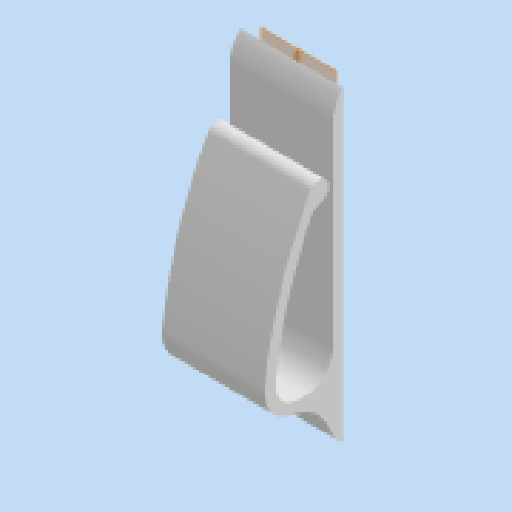
# Autodesk Inventor part: Pieza1
Saved by Autodesk Inventor 2026.3 (Build 303398000, 398)
## iProperties
Created: 2026-11-11
Part Number: Pieza1
Material: Genérico
Document SubType Name: Modeling
Designer: Hp
Density: 1 g/cm^3
Appearance: Valor por defecto
Author: Hp
Autodesk Inventor part; units mm, degrees
ref_plane "YZ Plane" through (0, 0, 0) normal (1, 0, 0) x (0, 1, 0)
ref_plane "XZ Plane" through (0, 0, 0) normal (0, 1, 0) x (-1, 0, 0)
ref_plane "Plano de trabajo1" through (0, 0, 0) normal (0, 0, 1) x (1, 0, 0)
sketch "Boceto1" plane through (0, 0, 0) normal (0, 0, 1) x (1, 0, 0)
  arc A0 (-5, -16) -> (5, -16) centre (0, -16) ccw projected
  line L0 (5, 16) -> (5, -16) projected
  arc A1 (5, 16) -> (-5, 16) centre (0, 16) ccw projected
  line L1 (-5, -16) -> (-5, 16) projected
  circle A2 centre (0, -16) radius 2.5 projected
  circle A3 centre (0, 16) radius 2.5 projected
  arc A4 (4.78, 16) -> (-4.78, 16) centre (0, 16) ccw
  line L2 (4.78, 16) -> (4.78, -16)
  arc A5 (-4.78, -16) -> (4.78, -16) centre (0, -16) ccw
  line L3 (-4.78, -16) -> (-4.78, 16)
  circle A6 centre (0, 16) radius 2.72
  circle A7 centre (0, -16) radius 2.72
  point P0 (0, 0)
  dimension "d0" = 0.22
  dimension "d1" = 0.22
  constraints: 4 centre point, 4 end point, 4 point on circle, 1 coincident, 1 equal radius, 3 other
  measures "d0" radial gap between concentric circles of A1 A4
  measures "d1" radial gap between concentric circles of A3 A6
ref_plane "Plano de trabajo2" through (-26.5719, -30.2815, 0.6) normal (0, 0, 1) x (1, 0, 0)
extrude "Extrusión1" add sketch "Boceto1" along normal blind 1 contours L2 A5 L3 A4
ref_plane "Plano de trabajo4" through (0, -16, 0) normal (-1, 0, 0) x (0, 0, 1)
sketch "Boceto4" plane through (0, 0, 1) normal (0, 0, 1) x (1, 0, 0)
  line L0 (7.5, 22.5) -> (-7.5, 22.5)
  line L1 (-7.5, 22.5) -> (-7.5, -22.5)
  line L2 (-7.5, -22.5) -> (7.5, -22.5)
  line L3 (7.5, -22.5) -> (7.5, 22.5)
  line L4 (0, -31.5) -> (0, 31.5) projected
  point P0 (0, 0)
  dimension "d22" = 45
  dimension "d23" = 15
  dimension "d24" = 7.5
  dimension "d25" = 22.5
  constraints: 8 end point, 2 parallel, 1 horizontal, 1 perpendicular
  measures "d22" distance of L2.end L0.start
  measures "d23" distance of L1.end L2.end
  measures "d24" distance between parallel lines of L3 L4
  measures "d25" distance from line of point (0, 0) L0
extrude "Extrusión4" add sketch "Boceto4" along normal blind 1.5
sketch "Boceto2" plane through (0, -16, 0) normal (-1, 0, 0) x (0, 0, 1)
  line L0 (2.5, 0.5467) -> (14.8168, 0.5467) construction
  line L1 (14.8168, 0.5467) -> (0.6, 37) construction
  arc A0 (7.5, 0.5467) -> (12.4705, 6.0892) centre (7.5, 5.5467) ccw
  arc A1 (12.4705, 6.0892) -> (5.825, 27.7031) centre (-47.1753, -0.4211) ccw
  arc A2 (12.1583, 7.3634) -> (3.8339, 2.1467) centre (7.5, 5.5467) ccw construction
  arc A3 (12.4705, 6.0892) -> (12.1583, 7.3634) centre (7.5, 5.5467) ccw
  arc A4 (10.8799, 5.9156) -> (4.4117, 26.9531) centre (-47.1753, -0.4211) ccw
  arc A5 (7.656, 2.1503) -> (7.6549, 2.1502) centre (7.5, 5.5467) ccw construction
  arc A6 (7.6549, 2.1502) -> (7.5, 2.1467) centre (7.5, 5.5467) ccw
  arc A7 (7.5, 2.1467) -> (7.656, 2.1503) centre (7.5, 5.5467) ccw
  line L2 (0.6, 37) -> (0, 37)
  arc A8 (5.825, 27.7031) -> (4.4117, 26.9531) centre (5.1183, 27.3281) ccw
  circle A9 centre (4.5, 27) radius 1.5
  arc A10 (5.6844, 24.4067) -> (4.2318, 25.5242) centre (3.8741, 23.5564) ccw
  line L3 (7.5, 0.5467) -> (2.5, 0.5467)
  line L4 (2.5, 2.1467) -> (7.5, 2.1467)
  line L5 (2.5, 0.5467) -> (2.5, 2.1467)
  line L6 (2.5, -6.5) -> (2.5, 38.5) projected
  arc A11 (7.0204, 2.1807) -> (6.5, 2.1467) centre (6.5, 6.1467) ccw
  arc A12 (6.5, 2.1467) -> (7.0204, 2.1807) centre (6.5, 6.1467) ccw
  point P0 (0, 16)
  point P1 (5.825, 27.7031)
  point P2 (10.8799, 5.9156)
  point P3 (10.3488, 9.6557)
  point P4 (5.0956, 25.6233)
  point P5 (5.825, 27.7031)
  point P6 (2.5, 1.3467)
  point P7 (10.8799, 5.9156)
  point P8 (7.6549, 2.1502)
  point P9 (2.5, 6.1467)
  dimension "d6" = 3
  dimension "d4" = 10
  dimension "d5" = 1.6
  dimension "d7" = 60
  dimension "d8" = 2
  dimension "d9" = 10
  dimension "d28" = 5
  dimension "d29" = 2
  dimension "d30" = 8
  constraints: 27 point on circle, 13 tangent, 12 centre point, 12 end point, 6 point on line, 3 horizontal, 1 collinear, 1 midpoint, 1 perpendicular, 8 other
  measures "d4" diameter of A0
  measures "d5" radial gap between concentric circles of A4 A1
  measures "d7" radius of A1
  measures "d8" radius of A10
  measures "d9" vertical distance of L1.end point (4.5, 27)
  measures "d28" distance of L3.start L0.start
  measures "d29" distance from line of L6 point (4.5, 27)
  measures "d30" diameter of A11
extrude "Extrusión2" add sketch "Boceto2" along normal mid plane 15 contours L3 L5 L4 A7 A6 A4 A9 A1 A0 | A9 A4 A8 | A8 A4 A9 | L6 A11 L4 | A9 A4 A10
fillet "Empalme5" radius 7 1 edges at (0, -15.4533, 2.5)
fillet "Empalme6" radius 5 2 edges at (0, 22.5, 2.5) (0, -22.5, 2.5)
equation "\"d24\" = 0.5 * d23"
equation "\"d25\" = 0.5 * d22"
